fusion-model (Autodesk Fusion 360 design; units mm, degrees)
part number: 2026-10-02-23-07-11-813
part number: 2026-10-02-23-07-24-127
Autodesk Fusion 360 part; units mm, degrees
sketch "Pod profile" plane through (0, 0, 0) normal (0, 1, 0) x (1, 0, 0)
  arc A0 (26.9117, -25.3922) -> (0, 37) centre (0, 0) ccw
  arc A1 (26.9117, -25.3922) -> (26.9117, -44.6078) centre (37.0945, -35) ccw
  arc A2 (26.9117, -95.3922) -> (26.9117, -44.6078) centre (0, -70) ccw
  arc A3 (26.9117, -95.3922) -> (26.9117, -114.6078) centre (37.0945, -105) ccw
  arc A4 (0, -177) -> (26.9117, -114.6078) centre (0, -140) ccw
  line L0 (0, -177) -> (0, 37)
revolve "Pod body" add sketch "Pod profile" angle 360 about axis through (0, 0, 1.75) along (0, 0, 1) makes body 1
ref_plane "WorkPlane1" through (0, 8.4891, 0) normal (0, 1, 0) x (0, 0, 1)
sketch "Sketch2" plane through (0, 8.4891, 0) normal (0, 1, 0) x (1, 0, 0)
  arc A0 (0, -184) -> (0, -168) centre (0, -176) ccw
  line L0 (0, -168) -> (0, -184)
revolve "Stem node" add sketch "Sketch2" angle 360 about axis through (0, 8.4891, 168) along (0, 0, 1) bodies 1
ref_plane "WorkPlane2" through (0, 10.0891, 0) normal (0, 1, 0) x (0, 0, 1)
sketch "Tendril path" plane through (0, 10.0891, 0) normal (0, 1, 0) x (1, 0, 0)
  spline S0 degree 5 poles (0, -169) (0.0136, -169.2974) (0.0382, -169.8949) (0.0676, -170.7987) (0.0916, -172.019) (0.0969, -173.5695) (0.0791, -175.1432) (0.0416, -176.7366) (-0.01, -178.3438) (-0.0671, -179.9556) (-0.1176, -181.5595) (-0.1475, -183.1416) (-0.1411, -184.6876) (-0.0823, -186.1854) (0.0446, -187.6254) (0.2543, -189.0037) (0.5591, -190.3211) (0.9687, -191.5812) (1.4898, -192.7873) (2.1248, -193.9409) (2.8715, -195.0384) (3.7233, -196.0708) (4.6701, -197.0262) (5.7001, -197.8915) (6.8009, -198.6542) (7.9607, -199.3052) (9.1692, -199.8388) (10.4165, -200.2523) (11.693, -200.5446) (12.9888, -200.7157) (14.2929, -200.7655) (15.5936, -200.6936) (16.8786, -200.5002) (18.1356, -200.1864) (19.3526, -199.7545) (20.5186, -199.2087) (21.6231, -198.5551) (22.6565, -197.801) (23.6098, -196.9542) (24.4744, -196.0232) (25.2421, -195.0161) (25.9055, -193.9414) (26.4579, -192.8083) (26.8943, -191.6276) (27.2111, -190.4117) (27.4068, -189.1753) (27.481, -187.9337) (27.4344, -186.7012) (27.268, -185.4905) (26.9828, -184.3101) (26.5797, -183.1653) (26.1633, -182.2798) (25.7983, -181.6331) (25.5315, -181.2097) (25.3923, -181) knots 0 0 0 0 0 0 0.02 0.04 0.06 0.08 0.1 0.12 0.14 0.16 0.18 0.2 0.22 0.24 0.26 0.28 0.3 0.32 0.34 0.36 0.38 0.4 0.42 0.44 0.46 0.48 0.5 0.52 0.54 0.56 0.58 0.6 0.62 0.64 0.66 0.68 0.7 0.72 0.74 0.76 0.78 0.8 0.82 0.84 0.86 0.88 0.9 0.92 0.94 0.96 0.98 1 1 1 1 1 1
  point P0 (0, -178)
  point P1 (0, -187)
  point P2 (1.8832, -193.4685)
  point P3 (6.3251, -198.3053)
  point P4 (12.2931, -200.6084)
  point P5 (18.4941, -200.04)
  point P6 (23.6539, -196.8679)
  point P7 (26.7795, -191.8792)
  point P8 (27.3485, -186.1906)
ref_plane "WorkPlane3" through (0, 10.0891, 169) normal (0.045595, 0, 0.99896) x (0, 1, 0)
sketch "Sketch4" plane through (0, 10.0891, 169) normal (0.045595, 0, 0.99896) x (0, 1, 0)
  circle A0 centre (0, 0) radius 4.5
sweep "Tendril hook" add profiles "Sketch4" path "Tendril path" along S0 section 1 bodies 1
sketch "Ball pockets" plane through (0, 0, 0) normal (0, 1, 0) x (1, 0, 0)
  arc A0 (0, -34) -> (0, 34) centre (0, 0) ccw
  line L0 (0, 34) -> (0, -34)
  arc A1 (0, -104) -> (0, -36) centre (0, -70) ccw
  line L1 (0, -36) -> (0, -104)
  arc A2 (0, -174) -> (0, -106) centre (0, -140) ccw
  line L2 (0, -106) -> (0, -174)
revolve "Ball pockets (1)" cut sketch "Ball pockets" angle 360 about axis through (0, 0, 1.75) along (0, 0, 1) bodies 1
ref_plane "WorkPlane4" through (0, 12.4891, 0) normal (0, 1, 0) x (0, 0, 1)
sketch "Front seam cut" plane through (0, 12.4891, 0) normal (0, 1, 0) x (1, 0, 0)
  line L0 (-70, 67) -> (70, 67)
  line L1 (70, 67) -> (70, -247)
  line L2 (70, -247) -> (-70, -247)
  line L3 (-70, -247) -> (-70, 67)
extrude "Front seam cut (1)" cut sketch "Front seam cut" along normal blind 80 bodies 1
sketch "Thumb windows" plane through (0, 0, 0) normal (0, 1, 0) x (1, 0, 0)
  circle A0 centre (0, 0) radius 24
  circle A1 centre (0, -70) radius 24
  circle A2 centre (0, -140) radius 24
extrude "Thumb windows (1)" cut sketch "Thumb windows" against normal blind 60 bodies 1
sketch "Seam groove" plane through (0, 0, 0) normal (0, 0, 1) x (1, 0, 0)
  line L0 (0, -5.5109) -> (21, 15.4891)
  line L1 (21, 15.4891) -> (-21, 15.4891)
  line L2 (-21, 15.4891) -> (0, -5.5109)
extrude "Seam groove (1)" cut sketch "Seam groove" along normal blind 140 bodies 1
chamfer "Lip lead-in chamfer" distance 1 angle 45 4 edges at (0, 12.4891, 171.6231) (-31.6231, 12.4891, 70) (0, 12.4891, -31.6231) (31.6231, 12.4891, 70) tangent chain off on bodies 1
fillet "Thumb window fillet" radius 1.5 6 edges at (-22.3759, -24.0832, -8.6788) (-22.3759, -28.1603, 8.6788) (-22.3759, -24.0832, 61.3212) (-22.3759, -28.1603, 78.6788) (-22.3759, -24.0832, 131.3212) (-22.3759, -28.1603, 148.6788) on bodies 1
fillet "Seam groove fillet" radius 1 18 edges at (17.5316, 12.0207, 42.8726) (17.5316, 12.0207, 27.1274) (8.9736, 3.4628, 32.6111) (0, -5.5109, 35) (8.9736, 3.4628, 37.3889) (-17.5316, 12.0207, 27.1274) (-17.5316, 12.0207, 42.8726) (-8.9736, 3.4628, 37.3889) (-8.9736, 3.4628, 32.6111) (-17.5316, 12.0207, 97.1274) (-17.5316, 12.0207, 112.8726) (-8.9736, 3.4628, 107.3889) (0, -5.5109, 105) (-8.9736, 3.4628, 102.6111) (17.5316, 12.0207, 97.1274) (8.9736, 3.4628, 102.6111) (8.9736, 3.4628, 107.3889) (17.5316, 12.0207, 112.8726) on bodies 1
fillet "Stem node fillet" radius 2.5 5 edges at (3.8262, 7.9584, 183.0056) (-4.0971, 7.9535, 182.8503) (-4.0971, 7.9535, 182.8503) (3.8262, 7.9584, 183.0056) (0, 0.5514, 176.9959) on bodies 1
sketch "Sketch1" plane through (0, 0, 0) normal (0, 1, 0) x (1, 0, 0) in component "Reference tennis balls"
  arc A0 (0, -33.5) -> (0, 33.5) centre (0, 0) ccw
  line L0 (0, 33.5) -> (0, -33.5)
  arc A1 (0, -103.5) -> (0, -36.5) centre (0, -70) ccw
  line L1 (0, -36.5) -> (0, -103.5)
  arc A2 (0, -173.5) -> (0, -106.5) centre (0, -140) ccw
  line L2 (0, -106.5) -> (0, -173.5)
revolve "Revolve1" add sketch "Sketch1" angle 360 about axis through (0, 0, 1.75) along (0, 0, 1) separate body makes body 2 at (31.7605, 7.9188, 7.1284) makes body 3 at (31.7605, 7.9188, 77.1284) makes body 4 at (31.7605, 7.9188, 147.1284) in component "Reference tennis balls"
move_body "Print orientation" bodies 1 to x (1, 0, 0) y (0, 0, -1) z (0, 1, 0) at (0, 0, 12.4891)
sketch "Sketch9" plane through (0, 0, 0) normal (1, 0, 0) x (0, 1, 0)
  spline S0 degree 5 poles (85.3545, 18.8007, 50) (85.0776, 19.1031, 50) (84.4995, 19.6893, 50) (83.5597, 20.5126, 50) (82.1604, 21.4978, 50) (80.1655, 22.5358, 50) (77.9306, 23.3719, 50) (75.4759, 23.9962, 50) (72.8464, 24.3984, 50) (70.1148, 24.5727, 50) (67.3672, 24.5175, 50) (64.6956, 24.2334, 50) (62.187, 23.7229, 50) (59.9152, 22.9899, 50) (57.9278, 22.0411, 50) (56.2449, 20.8847, 50) (55.1458, 19.7999, 50) (54.4592, 18.8989, 50) (54.0622, 18.2596, 50) (53.8788, 17.9304, 50) knots 0 0 0 0 0 0 0.06666667 0.13333333 0.2 0.26666667 0.33333333 0.4 0.46666667 0.53333333 0.6 0.66666667 0.73333333 0.8 0.86666667 0.93333333 1 1 1 1 1 1
  spline S1 degree 5 poles (85.3545, 18.8007, 50) (85.2025, 18.448, 50) (84.8599, 17.7637, 50) (84.2304, 16.8008, 50) (83.1581, 15.6445, 50) (81.4256, 14.418, 50) (79.308, 13.418, 50) (76.8328, 12.6527, 50) (74.064, 12.127, 50) (71.1041, 11.8419, 50) (68.0756, 11.7966, 50) (65.1096, 11.9891, 50) (62.331, 12.4167, 50) (59.8468, 13.0754, 50) (57.7284, 13.9591, 50) (56.0073, 15.0594, 50) (54.9551, 16.1065, 50) (54.347, 16.9832, 50) (54.0216, 17.6079, 50) (53.8788, 17.9304, 50) knots 0 0 0 0 0 0 0.06666667 0.13333333 0.2 0.26666667 0.33333333 0.4 0.46666667 0.53333333 0.6 0.66666667 0.73333333 0.8 0.86666667 0.93333333 1 1 1 1 1 1
  line L0 (83.2461, 20.6847, 50) -> (87.9133, 25.4444, 50)
  line L1 (87.9133, 25.4444, 50) -> (87.9133, 12.1831, 50)
  line L2 (87.9133, 12.1831, 50) -> (83.7024, 16.3121, 50)
  line L3 (65.428, 24.2743, 50) -> (72.1673, 28.3808, 50)
  line L4 (72.1673, 28.3808, 50) -> (72.5193, 24.3724, 50)
  line L5 (79.0409, 23.1775, 50) -> (72.3129, 24.6027, 50)
  point P0 (75.6769, 23.8901)
  point P1 (60.9862, 23.2972)
  point P2 (77.812, 12.9987)
  point P3 (60.8412, 12.8536)
scale "Scale1" [no effect]
sketch "Sketch11" plane through (50, 0, 0) normal (1, 0, 0) x (0, 1, 0)
  spline S0 degree 3 poles (81.4671, 12.2932, -17.9927) (80.6725, 13.1725, -17.7026) (79.8337, 14.0764, -17.4669) (78.962, 14.9895, -17.2978) knots 0 0 0 0 0.58974998 0.58974998 0.58974998 0.58974998
  spline S1 degree 3 poles (78.5997, 17.8099, -17.5387) (79.5043, 18.7747, -17.9365) (80.3536, 19.6901, -18.4001) (81.1407, 20.5463, -18.9039) knots 0 0 0 0 0.66661182 0.66661182 0.66661182 0.66661182
  spline S2 degree 3 poles (81.1407, 20.5463, -18.9039) (81.3498, 18.0045, -18.3202) (81.4679, 15.2385, -17.9904) (81.4673, 12.4665, -17.9922) (81.4673, 12.4087, -17.9922) (81.4672, 12.351, -17.9924) (81.4671, 12.2932, -17.9927) knots 0 0 0 0 1.29906793 1.29906793 1.29906793 1.32613184 1.32613184 1.32613184 1.32613184
  spline S3 degree 3 poles (79.9092, 16.5623, -17.7321) (79.6252, 16.8933, -17.6867) (79.3145, 17.2059, -17.6396) (78.9763, 17.4997, -17.5913) (78.638, 17.7934, -17.5431) (78.2722, 18.0683, -17.4936) (77.8779, 18.3234, -17.4439) (77.4837, 18.5784, -17.3942) (77.061, 18.8136, -17.3443) (76.6099, 19.0275, -17.2959) (76.1588, 19.2413, -17.2475) (75.6793, 19.4337, -17.2005) (75.1733, 19.6027, -17.1574) (74.6673, 19.7717, -17.1143) (74.1347, 19.9173, -17.0751) (73.5808, 20.0374, -17.0424) (73.0269, 20.1575, -17.0098) (72.4516, 20.2521, -16.9837) (71.8637, 20.3196, -16.9665) (71.2758, 20.3871, -16.9494) (70.6754, 20.4275, -16.9411) (70.0733, 20.4402, -16.9428) (70.0487, 20.4407, -16.9429) (70.0241, 20.4411, -16.943) (69.9995, 20.4416, -16.9431) (69.4219, 20.4516, -16.9455) (68.8432, 20.4361, -16.9571) (68.2737, 20.3955, -16.9772) (67.6799, 20.3532, -16.9981) (67.0961, 20.2836, -17.0282) (66.5328, 20.1878, -17.0651) (65.9695, 20.092, -17.102) (65.4266, 19.97, -17.1456) (64.9122, 19.8236, -17.1927) (64.3979, 19.6772, -17.2397) (63.912, 19.5064, -17.2901) (63.459, 19.3129, -17.3404) (63.006, 19.1194, -17.3907) (62.5858, 18.9034, -17.4409) (62.1997, 18.6663, -17.4885) (61.8136, 18.4293, -17.5361) (61.4614, 18.1713, -17.5811) (61.1427, 17.8935, -17.6219) (60.824, 17.6156, -17.6627) (60.5386, 17.3179, -17.6994) (60.2855, 17.0009, -17.7312) (60.0324, 16.6839, -17.7631) (59.8115, 16.3476, -17.7902) (59.622, 15.9919, -17.8126) knots 0 0 0 0 0.06666667 0.06666667 0.06666667 0.13333333 0.13333333 0.13333333 0.2 0.2 0.2 0.26666667 0.26666667 0.26666667 0.33333333 0.33333333 0.33333333 0.4 0.4 0.4 0.46666667 0.46666667 0.46666667 0.46938776 0.46938776 0.46938776 0.53333333 0.53333333 0.53333333 0.6 0.6 0.6 0.66666667 0.66666667 0.66666667 0.73333333 0.73333333 0.73333333 0.8 0.8 0.8 0.86666667 0.86666667 0.86666667 0.93333333 0.93333333 0.93333333 1 1 1 1
  spline S4 degree 3 poles (82.1237, 21.2572, -16.1601) (82.3512, 18.4911, -15.5249) (82.4798, 15.4811, -15.1661) (82.4791, 12.4645, -15.168) (82.4791, 12.4016, -15.168) (82.479, 12.3388, -15.1682) (82.4789, 12.2759, -15.1685) knots 0 0 0 0 1.29906793 1.29906793 1.29906793 1.32613184 1.32613184 1.32613184 1.32613184
  spline S5 degree 3 poles (80.7835, 16.9217, -14.8849) (80.4745, 17.2819, -14.8355) (80.1364, 17.6221, -14.7843) (79.7683, 17.9418, -14.7318) (79.4002, 18.2614, -14.6792) (79.0021, 18.5606, -14.6254) (78.573, 18.8381, -14.5713) (78.144, 19.1157, -14.5172) (77.684, 19.3717, -14.4629) (77.1931, 19.6044, -14.4102) (76.7022, 19.8371, -14.3575) (76.1804, 20.0464, -14.3065) (75.6297, 20.2304, -14.2596) (75.0791, 20.4143, -14.2127) (74.4995, 20.5728, -14.17) (73.8968, 20.7035, -14.1344) (73.294, 20.8342, -14.0989) (72.668, 20.9371, -14.0705) (72.0282, 21.0105, -14.0518) (71.3884, 21.0839, -14.0331) (70.735, 21.1279, -14.0242) (70.0797, 21.1417, -14.026) (70.053, 21.1423, -14.0261) (70.0263, 21.1428, -14.0262) (69.9995, 21.1433, -14.0263) (69.3709, 21.1542, -14.0289) (68.7412, 21.1374, -14.0416) (68.1214, 21.0932, -14.0634) (67.4752, 21.0471, -14.0861) (66.8399, 20.9713, -14.1189) (66.2269, 20.8671, -14.1591) (65.6138, 20.7628, -14.1992) (65.0231, 20.6301, -14.2467) (64.4633, 20.4708, -14.2979) (63.9036, 20.3115, -14.3491) (63.3748, 20.1255, -14.4039) (62.8818, 19.915, -14.4586) (62.3889, 19.7045, -14.5134) (61.9316, 19.4694, -14.568) (61.5114, 19.2114, -14.6198) (61.0913, 18.9534, -14.6716) (60.708, 18.6727, -14.7206) (60.3612, 18.3703, -14.765) (60.0143, 18.068, -14.8094) (59.7038, 17.744, -14.8493) (59.4284, 17.399, -14.884) (59.1529, 17.0541, -14.9187) (58.9125, 16.6881, -14.9482) (58.7063, 16.301, -14.9725) knots 0 0 0 0 0.06666667 0.06666667 0.06666667 0.13333333 0.13333333 0.13333333 0.2 0.2 0.2 0.26666667 0.26666667 0.26666667 0.33333333 0.33333333 0.33333333 0.4 0.4 0.4 0.46666667 0.46666667 0.46666667 0.46938776 0.46938776 0.46938776 0.53333333 0.53333333 0.53333333 0.6 0.6 0.6 0.66666667 0.66666667 0.66666667 0.73333333 0.73333333 0.73333333 0.8 0.8 0.8 0.86666667 0.86666667 0.86666667 0.93333333 0.93333333 0.93333333 1 1 1 1
  spline S6 degree 3 poles (82.4789, 12.2759, -15.1685) (81.6142, 13.2328, -14.8529) (80.7013, 14.2165, -14.5963) (79.7527, 15.2102, -14.4124) knots 0 0 0 0 0.58974998 0.58974998 0.58974998 0.58974998
  spline S7 degree 3 poles (79.3585, 18.2794, -14.6745) (80.343, 19.3294, -15.1074) (81.2672, 20.3255, -15.6119) (82.1237, 21.2572, -16.1601) knots 0 0 0 0 0.66661182 0.66661182 0.66661182 0.66661182
  spline S8 degree 3 poles (79.9092, 16.5623, -17.7321) (79.7728, 16.1941, -17.6437) (79.5946, 15.8459, -17.5525) (79.373, 15.5181, -17.4581) (79.1514, 15.1903, -17.3638) (78.8864, 14.883, -17.2664) (78.5761, 14.5971, -17.167) (78.2658, 14.3112, -17.0676) (77.9101, 14.0467, -16.9662) (77.508, 13.8049, -16.8654) (77.1059, 13.5631, -16.7647) (76.6572, 13.3441, -16.6647) (76.1638, 13.1494, -16.5699) (75.6703, 12.9547, -16.4751) (75.1319, 12.7843, -16.3855) (74.5551, 12.6397, -16.3069) (73.9784, 12.4951, -16.2282) (73.3633, 12.3763, -16.1607) (72.7223, 12.2844, -16.1098) (72.0814, 12.1925, -16.0588) (71.4147, 12.1275, -16.0246) (70.7389, 12.0899, -16.0104) (70.5045, 12.0768, -16.0054) (70.269, 12.0671, -16.0029) (70.0331, 12.0606, -16.0027) (69.5892, 12.0484, -16.0024) (69.1441, 12.0479, -16.0108) (68.703, 12.059, -16.0275) (68.0276, 12.0759, -16.053) (67.3616, 12.1201, -16.0984) (66.7217, 12.1905, -16.1597) (66.0819, 12.2609, -16.2211) (65.4683, 12.3576, -16.2984) (64.8935, 12.4792, -16.3857) (64.3187, 12.6009, -16.4729) (63.7829, 12.7475, -16.5701) (63.2928, 12.9174, -16.6709) (62.8027, 13.0873, -16.7717) (62.3582, 13.2806, -16.8761) (61.9611, 13.4957, -16.9793) (61.564, 13.7108, -17.0826) (61.2141, 13.9476, -17.1846) (60.9102, 14.2051, -17.2826) (60.6063, 14.4626, -17.3805) (60.3484, 14.7407, -17.4743) (60.1343, 15.0386, -17.5629) (59.9203, 15.3366, -17.6514) (59.75, 15.6544, -17.7346) (59.622, 15.9919, -17.8126) knots 0 0 0 0 0.06666667 0.06666667 0.06666667 0.13333333 0.13333333 0.13333333 0.2 0.2 0.2 0.26666667 0.26666667 0.26666667 0.33333333 0.33333333 0.33333333 0.4 0.4 0.4 0.46666667 0.46666667 0.46666667 0.48979592 0.48979592 0.48979592 0.53333333 0.53333333 0.53333333 0.6 0.6 0.6 0.66666667 0.66666667 0.66666667 0.73333333 0.73333333 0.73333333 0.8 0.8 0.8 0.86666667 0.86666667 0.86666667 0.93333333 0.93333333 0.93333333 1 1 1 1
  spline S9 degree 3 poles (71.4033, 22.7791, -17.6249) (71.49, 21.9922, -17.3785) (71.5774, 21.178, -17.1555) (71.6647, 20.3413, -16.9611) knots 0 0 0 0 0.40238671 0.40238671 0.40238671 0.40238671
  spline S10 degree 3 poles (66.9859, 20.2586, -17.0371) (68.4735, 21.1439, -17.1098) (69.9623, 21.9921, -17.3123) (71.4033, 22.7791, -17.6249) knots 0 0 0 0 0.78918486 0.78918486 0.78918486 0.78918486
  spline S11 degree 3 poles (80.7835, 16.9217, -14.8849) (80.6351, 16.521, -14.7888) (80.4412, 16.1421, -14.6895) (80.2, 15.7853, -14.5868) (79.9589, 15.4286, -14.4842) (79.6705, 15.0942, -14.3781) (79.3328, 14.7831, -14.27) (78.9951, 14.4719, -14.1618) (78.608, 14.1841, -14.0514) (78.1704, 13.921, -13.9418) (77.7328, 13.6579, -13.8322) (77.2446, 13.4196, -13.7234) (76.7076, 13.2077, -13.6202) (76.1706, 12.9957, -13.517) (75.5847, 12.8103, -13.4195) (74.9571, 12.653, -13.3339) (74.3294, 12.4956, -13.2484) (73.66, 12.3664, -13.1749) (72.9625, 12.2664, -13.1195) (72.265, 12.1663, -13.064) (71.5395, 12.0956, -13.0268) (70.8041, 12.0547, -13.0113) (70.549, 12.0404, -13.0059) (70.2927, 12.0298, -13.0031) (70.036, 12.0228, -13.003) (69.5529, 12.0095, -13.0027) (69.0686, 12.009, -13.0117) (68.5886, 12.021, -13.0299) (67.8536, 12.0395, -13.0577) (67.1288, 12.0875, -13.107) (66.4325, 12.1641, -13.1738) (65.7362, 12.2408, -13.2406) (65.0684, 12.346, -13.3247) (64.4429, 12.4784, -13.4197) (63.8174, 12.6108, -13.5147) (63.2343, 12.7703, -13.6204) (62.701, 12.9552, -13.7301) (62.1676, 13.1401, -13.8398) (61.684, 13.3504, -13.9534) (61.2518, 13.5845, -14.0658) (60.8197, 13.8185, -14.1781) (60.4389, 14.0763, -14.2892) (60.1082, 14.3565, -14.3957) (59.7775, 14.6367, -14.5023) (59.4968, 14.9393, -14.6044) (59.2638, 15.2636, -14.7008) (59.0309, 15.5879, -14.7971) (58.8456, 15.9337, -14.8877) (58.7063, 16.301, -14.9725) knots 0 0 0 0 0.06666667 0.06666667 0.06666667 0.13333333 0.13333333 0.13333333 0.2 0.2 0.2 0.26666667 0.26666667 0.26666667 0.33333333 0.33333333 0.33333333 0.4 0.4 0.4 0.46666667 0.46666667 0.46666667 0.48979592 0.48979592 0.48979592 0.53333333 0.53333333 0.53333333 0.6 0.6 0.6 0.66666667 0.66666667 0.66666667 0.73333333 0.73333333 0.73333333 0.8 0.8 0.8 0.86666667 0.86666667 0.86666667 0.93333333 0.93333333 0.93333333 1 1 1 1
  spline S12 degree 3 poles (66.7199, 20.9441, -14.1286) (68.3388, 21.9075, -14.2077) (69.959, 22.8306, -14.4281) (71.5271, 23.687, -14.7683) knots 0 0 0 0 0.78918486 0.78918486 0.78918486 0.78918486
  spline S13 degree 3 poles (71.5271, 23.687, -14.7683) (71.6214, 22.8307, -14.5002) (71.7165, 21.9447, -14.2575) (71.8116, 21.0342, -14.0459) knots 0 0 0 0 0.40238671 0.40238671 0.40238671 0.40238671
  point P0 (71.527, 20.4867)
  point P1 (75.9202, 19.4881)
  point P2 (71.527, 20.4867)
  point P3 (75.9202, 19.4881)
sketch "Sketch12" plane through (50, 0, 0) normal (1, 0, 0) x (0, 1, 0)
sketch "Sketch13" plane through (50, 0, 0) normal (1, 0, 0) x (0, 1, 0)
extrude "Extrude5" cut sketch "Sketch9" against normal blind 40 contours S0 S1 | S0 S1 L0 L1 L2 | S0 L3 L4 in plane through (50, 0, 0) normal (1, 0, 0) bodies 1
fillet "Fillet4" radius 0.5 1 edges at (31.6611, 72.1673, 28.3808) on bodies 1
fillet "Fillet5" radius 1 1 edges at (31.8918, 83.2461, 20.6847) on bodies 1
fillet "Fillet6" radius 0.5 1 edges at (32.5184, 83.7024, 16.3121) on bodies 1
component "Reference tennis balls" placed x (1, 0, 0) y (0, 1, 0) z (0, 0, 1) at (0, 0, 0)
equation "ball_d = 67.0 mm" comment "measured tennis ball diameter"
equation "fit_clear = 1.0 mm" comment "pocket clearance over the ball"
equation "wall = 3.0 mm" comment "shell wall"
equation "web = 2.0 mm" comment "septum between balls"
equation "lip_open = 64.0 mm" comment "snap opening of the front seam"
equation "back_win_d = 48.0 mm" comment "thumb push-out window"
equation "tendril_d = 9.0 mm" comment "hanging hook tube"
equation "d29 = -( 60 mm )"
named bodies: "Pea pod", "Tennis ball 1", "Tennis ball 2", "Tennis ball 3"
